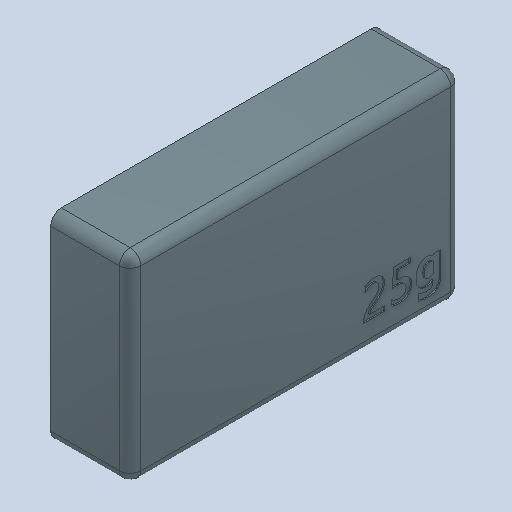
# Autodesk Inventor part: weight
Saved by Autodesk Inventor 2026.1 (Build 301233020, 233B)
## iProperties
Created: 2026-01-07
Part Number: weight
Material: Piombo
Document SubType Name: Modeling
Designer: maxbu
Mass: 25.3569 g
Surface Area: 11.9338 cm^2
Volume: 2.23606 cm^3
Density: 11.34 g/cm^3
Appearance: Piombo
Author: maxbu
Autodesk Inventor part; units mm, degrees
ref_plane "YZ Plane" through (0, 0, 0) normal (1, 0, 0) x (0, 1, 0)
ref_plane "XZ Plane" through (0, 0, 0) normal (0, 1, 0) x (-1, 0, 0)
ref_plane "XY Plane" through (0, 0, 0) normal (0, 0, 1) x (1, 0, 0)
sketch "Schizzo1" plane through (0, 0, 0) normal (1, 0, 0) x (0, 1, 0)
  line L0 (0, 0) -> (15, 0)
  line L1 (15, 0) -> (15, -25)
  line L2 (15, -25) -> (0, -25)
  line L3 (0, -25) -> (0, 0)
  dimension "d0" = 15
  dimension "d1" = 25
  constraints: 8 end point, 2 parallel, 1 horizontal, 1 perpendicular
  measures "d0" distance of L1.end L2.end
  measures "d1" distance of L0.end L1.end
extrude "Estrusione1" add sketch "Schizzo1" along normal blind 6
fillet "Raccordo1" radius 0.8 8 edges at (3, 15, 0) (6, 7.5, 0) (6, 15, -12.5) (3, 0, 0) (6, 0, -12.5) (6, 7.5, -25) (3, 15, -25) (3, 0, -25)
sketch "Schizzo2" plane through (6, 0, 0) normal (1, 0, 0) x (0, 0, -1)
  line L0 (17.4661, 4.6166) -> (27.4783, 4.6166) construction
  line L1 (27.4783, 4.6166) -> (27.4783, -0.5277) construction
  line L2 (27.4783, -0.5277) -> (17.4661, -0.5277) construction
  line L3 (17.4661, -0.5277) -> (17.4661, 4.6166) construction
  line L4 (19.2333, 2.0342) -> (17.6405, 2.0342)
  line L5 (17.6405, 2.0342) -> (17.6405, 2.2321)
  spline S0 degree 2 poles (17.6405, 2.2321) (17.6405, 2.3523) (17.7064, 2.562) (17.8195, 2.7482) (17.9727, 2.9131) (18.1471, 3.0686) (18.3261, 3.21) (18.4133, 3.283) knots 0 0 0 1 2 3 4 5 6 6 6
  spline S1 degree 2 poles (18.4133, 3.283) (18.4958, 3.3537) (18.6301, 3.4856) (18.7267, 3.627) (18.7785, 3.7849) (18.7785, 3.8768) knots 0 0 0 1 2 3 4 4 4
  spline S2 degree 2 poles (18.7785, 3.8768) (18.7785, 3.9781) (18.7173, 4.1265) (18.6065, 4.2279) (18.4534, 4.2797) (18.3615, 4.2797) knots 0 0 0 1 2 3 4 4 4
  spline S3 degree 2 poles (18.3615, 4.2797) (18.206, 4.2797) (17.8832, 4.1336) (17.7347, 3.9899) knots 0 0 0 1 2 2 2
  line L6 (17.7347, 3.9899) -> (17.7347, 4.3857)
  spline S4 degree 2 poles (17.7347, 4.3857) (17.8125, 4.4423) (17.9727, 4.5295) (18.1423, 4.5884) (18.3308, 4.6166) (18.4369, 4.6166) knots 0 0 0 1 2 3 4 4 4
  spline S5 degree 2 poles (18.4369, 4.6166) (18.6089, 4.6166) (18.8893, 4.5271) (19.0872, 4.3504) (19.1956, 4.0888) (19.1956, 3.9192) knots 0 0 0 1 2 3 4 4 4
  spline S6 degree 2 poles (19.1956, 3.9192) (19.1956, 3.766) (19.1202, 3.5186) (18.9788, 3.3066) (18.7809, 3.1157) (18.6584, 3.0144) knots 0 0 0 1 2 3 4 4 4
  spline S7 degree 2 poles (18.6584, 3.0144) (18.5547, 2.9319) (18.352, 2.7741) (18.1895, 2.6233) (18.0882, 2.4725) (18.0882, 2.3971) knots 0 0 0 1 2 3 4 4 4
  line L7 (18.0882, 2.3971) -> (18.0882, 2.3877)
  line L8 (18.0882, 2.3877) -> (19.2333, 2.3877)
  line L9 (19.2333, 2.3877) -> (19.2333, 2.0342)
  line L10 (19.7564, 2.0908) -> (19.7564, 2.4866)
  spline S8 degree 2 poles (19.7564, 2.4866) (20.0061, 2.3193) (20.2629, 2.3193) knots 0 0 0 1 1 1
  spline S9 degree 2 poles (20.2629, 2.3193) (20.5198, 2.3193) (20.8355, 2.5832) (20.8355, 2.8023) knots 0 0 0 1 2 2 2
  spline S10 degree 2 poles (20.8355, 2.8023) (20.8355, 3.0191) (20.5151, 3.2595) (20.2158, 3.2595) knots 0 0 0 1 2 2 2
  spline S11 degree 2 poles (20.2158, 3.2595) (20.1121, 3.2595) (19.7988, 3.2382) knots 0 0 0 1 1 1
  line L11 (19.7988, 3.2382) -> (19.8907, 4.5742)
  line L12 (19.8907, 4.5742) -> (21.1418, 4.5742)
  line L13 (21.1418, 4.5742) -> (21.1418, 4.2231)
  line L14 (21.1418, 4.2231) -> (20.2323, 4.2231)
  line L15 (20.2323, 4.2231) -> (20.1899, 3.587)
  spline S12 degree 2 poles (20.1899, 3.587) (20.3124, 3.594) (20.4114, 3.594) knots 0 0 0 1 1 1
  spline S13 degree 2 poles (20.4114, 3.594) (20.8143, 3.594) (21.2549, 3.1793) (21.2549, 2.8188) knots 0 0 0 1 2 2 2
  spline S14 degree 2 poles (21.2549, 2.8188) (21.2549, 2.4418) (20.7507, 1.9871) (20.3101, 1.9871) knots 0 0 0 1 2 2 2
  spline S15 degree 2 poles (20.3101, 1.9871) (19.9378, 1.9871) (19.7564, 2.0908) knots 0 0 0 1 1 1
  spline S16 degree 2 poles (23.4651, 2.2545) (23.4651, 1.9889) (23.3107, 1.6164) (23.179, 1.5135) knots 0 0 0 1 2 2 2
  spline S17 degree 2 poles (23.179, 1.5135) (23.0452, 1.4085) (22.6747, 1.3138) (22.4483, 1.3138) knots 0 0 0 1 2 2 2
  spline S18 degree 2 poles (22.4483, 1.3138) (22.2568, 1.3138) (21.9131, 1.3632) (21.7875, 1.3961) knots 0 0 0 1 2 2 2
  line L16 (21.7875, 1.3961) -> (21.7875, 1.8757)
  line L17 (21.7875, 1.8757) -> (21.8575, 1.8757)
  spline S19 degree 2 poles (21.8575, 1.8757) (21.9007, 1.8593) (22.0222, 1.8181) (22.0839, 1.8016) knots 0 0 0 1 2 2 2
  spline S20 degree 2 poles (22.0839, 1.8016) (22.158, 1.7831) (22.298, 1.7584) (22.37, 1.7584) knots 0 0 0 1 2 2 2
  spline S21 degree 2 poles (22.37, 1.7584) (22.5224, 1.7584) (22.7241, 1.8201) (22.7755, 1.8778) knots 0 0 0 1 2 2 2
  spline S22 degree 2 poles (22.7755, 1.8778) (22.827, 1.9375) (22.8682, 2.098) (22.8682, 2.2215) knots 0 0 0 1 2 2 2
  line L18 (22.8682, 2.2215) -> (22.8682, 2.2565)
  spline S23 degree 2 poles (22.8682, 2.2565) (22.7673, 2.168) (22.5038, 2.061) (22.3639, 2.061) knots 0 0 0 1 2 2 2
  spline S24 degree 2 poles (22.3639, 2.061) (21.9913, 2.061) (21.5879, 2.5447) (21.5879, 3.0407) knots 0 0 0 1 2 2 2
  spline S25 degree 2 poles (21.5879, 3.0407) (21.5879, 3.2651) (21.7114, 3.6233) (21.8225, 3.7488) knots 0 0 0 1 2 2 2
  spline S26 degree 2 poles (21.8225, 3.7488) (21.9295, 3.8703) (22.228, 4.002) (22.3906, 4.002) knots 0 0 0 1 2 2 2
  spline S27 degree 2 poles (22.3906, 4.002) (22.5368, 4.002) (22.7694, 3.9279) (22.864, 3.8661) knots 0 0 0 1 2 2 2
  line L19 (22.864, 3.8661) -> (22.8867, 3.9505)
  line L20 (22.8867, 3.9505) -> (23.4651, 3.9505)
  line L21 (23.4651, 3.9505) -> (23.4651, 2.2545)
  line L22 (22.8682, 2.6373) -> (22.8682, 3.5059)
  spline S28 degree 2 poles (22.8682, 3.5059) (22.8249, 3.5265) (22.6953, 3.5533) (22.6294, 3.5533) knots 0 0 0 1 2 2 2
  spline S29 degree 2 poles (22.6294, 3.5533) (22.4153, 3.5533) (22.1992, 3.2754) (22.1992, 3.0263) knots 0 0 0 1 2 2 2
  spline S30 degree 2 poles (22.1992, 3.0263) (22.1992, 2.9028) (22.2321, 2.7299) (22.2754, 2.6641) knots 0 0 0 1 2 2 2
  spline S31 degree 2 poles (22.2754, 2.6641) (22.3186, 2.5982) (22.4565, 2.5323) (22.5635, 2.5323) knots 0 0 0 1 2 2 2
  spline S32 degree 2 poles (22.5635, 2.5323) (22.6438, 2.5323) (22.7982, 2.5879) (22.8682, 2.6373) knots 0 0 0 1 2 2 2
  point P0 (0, 0)
  constraints: 2 other
emboss "Sbalzo1" sketch "Schizzo2" operation cut depth 0.1 direction (-1, 0, 0)
